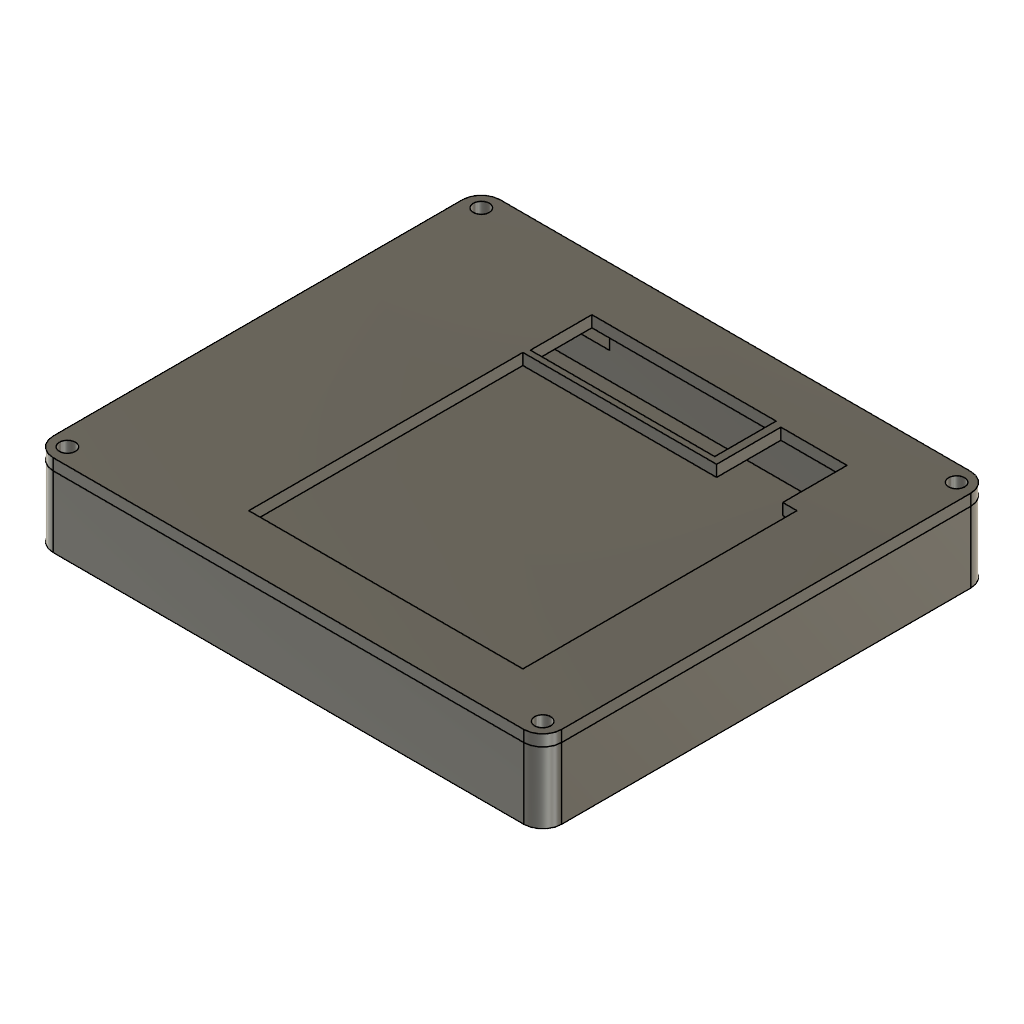
nexpad-case (Autodesk Fusion 360 design; units mm, degrees)
part number: 2026-11-12-22-31-13-139
Autodesk Fusion 360 part; units mm, degrees
sketch "Sketch1" plane through (0, 0, 0) normal (0, 0, 1) x (1, 0, 0)
sketch "base block" plane through (0, 0, 0) normal (0, 0, 1) x (1, 0, 0)
  line L0 (0, 0) -> (94, 0)
  line L1 (94, 0) -> (94, 81)
  line L2 (94, 81) -> (0, 81)
  line L3 (0, 81) -> (0, 0)
  line L4 (-7, -7) -> (100.6, -7)
  line L5 (100.6, -7) -> (100.6, 87.6)
  line L6 (100.6, 87.6) -> (-7, 87.6)
  line L7 (-7, 87.6) -> (-7, -7)
  dimension "d5" = 81
  dimension "d6" = 94
  dimension "d8" = 107.6
  dimension "d9" = 94.6
  constraint horizontal L0
  constraint vertical L1
  constraint horizontal L2
  constraint vertical L3
  constraint coincident L0.start L3.end
  constraint horizontal L4
  constraint vertical L5
  constraint horizontal L6
  constraint vertical L7
  measures "d5" distance of L0.end L1.end
  measures "d6" distance of L1.end L2.end
  measures "d8" distance of L4.start L4.end
  measures "d9" distance of L4.end L5.end
extrude "Extrude1" add sketch "base block" along normal blind 15 contours L0 L1 L2 L3 | L4 L5 L6 L7 makes body 1
fillet "Fillet1" radius 4 4 edges at (100.6, -7, 7.5) (100.6, 87.6, 7.5) (-7, 87.6, 7.5) (-7, -7, 7.5) on bodies 1
sketch "Sketch3" plane through (0, 0, 0) normal (0, 0, 1) x (1, 0, 0)
  line L0 (-0.35, -0.35) -> (93.95, -0.35)
  line L1 (93.95, -0.35) -> (93.95, 80.95)
  line L2 (93.95, 80.95) -> (-0.35, 80.95)
  line L3 (-0.35, 80.95) -> (-0.35, -0.35)
  dimension "d16" = 81.3
  dimension "d17" = 94.3
  dimension "d19" = 0.35
  dimension "d20" = 0.35
  constraint horizontal L0
  constraint vertical L1
  constraint horizontal L2
  constraint vertical L3
  measures "d16" distance of L0.start L2.end
  measures "d17" distance of L0.start L0.end
  measures "d19" distance of L3 origin
  measures "d20" distance of L0 origin
extrude "Extrude2" cut sketch "Sketch3" along normal blind 13 from surface at 2.4 bodies 1
fillet "Fillet2" radius 2.35 4 edges at (93.95, 80.95, 8.7) (-0.35, 80.95, 8.7) (93.95, -0.35, 8.7) (-0.35, -0.35, 8.7) on bodies 1
sketch "Sketch4" plane through (0, 0, 0) normal (0, 0, 1) x (1, 0, 0)
  line L0 (-1, -1) -> (3, -1)
  line L1 (3, -1) -> (3, 3)
  line L2 (3, 3) -> (-1, 3)
  line L3 (-1, 3) -> (-1, -1)
  line L4 (90.6, -1) -> (94.6, -1)
  line L5 (94.6, -1) -> (94.6, 3)
  line L6 (94.6, 3) -> (90.6, 3)
  line L7 (90.6, 3) -> (90.6, -1)
  line L8 (-1, 81.6) -> (3, 81.6)
  line L9 (3, 81.6) -> (3, 77.6)
  line L10 (3, 77.6) -> (-1, 77.6)
  line L11 (-1, 77.6) -> (-1, 81.6)
  line L12 (90.6, 81.6) -> (94.6, 81.6)
  line L13 (94.6, 81.6) -> (94.6, 77.6)
  line L14 (94.6, 77.6) -> (90.6, 77.6)
  line L15 (90.6, 77.6) -> (90.6, 81.6)
  dimension "d26" = 4
  dimension "d27" = 4
  dimension "d28" = 1
  dimension "d29" = 1
  dimension "d30" = 90.6
  dimension "d31" = 1
  dimension "d32" = 77.6
  dimension "d33" = 4
  dimension "d34" = 4
  dimension "d35" = 90.6
  dimension "d36" = 77.6
  constraint horizontal L0
  constraint vertical L1
  constraint horizontal L2
  constraint vertical L3
  constraint horizontal L4
  constraint vertical L5
  constraint horizontal L6
  constraint vertical L7
  constraint horizontal L8
  constraint vertical L9
  constraint horizontal L10
  constraint vertical L11
  constraint horizontal L12
  constraint vertical L13
  constraint horizontal L14
  constraint vertical L15
  measures "d26" distance of L0.start L0.end
  measures "d27" distance of L0.start L2.end
  measures "d28" distance of origin L3
  measures "d29" distance of origin L0
  measures "d30" distance of origin L7
  measures "d31" distance of origin L11
  measures "d32" distance of origin L10
  measures "d33" distance of L12.start L14.end
  measures "d34" distance of L12.start L12.end
  measures "d35" distance of origin L15
  measures "d36" distance of origin L14
extrude "Extrude3" add sketch "Sketch4" along normal blind 5.6 from surface at 2.4 bodies 1
sketch "Sketch5" plane through (0, 0, 0) normal (0, 0, 1) x (1, 0, 0)
  line L0 (4.8, 80) -> (26.8, 80)
  line L1 (26.8, 80) -> (26.8, 90)
  line L2 (26.8, 90) -> (4.8, 90)
  line L3 (4.8, 90) -> (4.8, 80)
  dimension "d40" = 22
  dimension "d41" = 10
  dimension "d42" = 4.8
  dimension "d43" = 80
  constraint horizontal L0
  constraint vertical L1
  constraint horizontal L2
  constraint vertical L3
  measures "d40" distance of L0.start L0.end
  measures "d41" distance of L0.start L2.end
  measures "d42" distance of origin L3
  measures "d43" distance of origin L0
extrude "Extrude4" cut sketch "Sketch5" along normal blind 10 from surface at 8 bodies 1
sketch "Sketch6" plane through (0, 0, 0) normal (0, 0, 1) x (1, 0, 0)
  circle A0 centre (-3.5, -3.5) radius 1.3
  circle A1 centre (97.1, -3.5) radius 1.3
  circle A2 centre (-3.5, 84.1) radius 1.3
  circle A3 centre (97.1, 84.1) radius 1.3
  dimension "d47" = 2.6
  dimension "d48" = 3.5
  dimension "d50" = 3.5
  dimension "d51" = 2.6
  dimension "d52" = 3.5
  dimension "d54" = 97.1
  dimension "d55" = 2.6
  dimension "d56" = 3.5
  dimension "d57" = 84.1
  dimension "d58" = 2.6
  dimension "d59" = 97.1
  dimension "d60" = 84.1
  measures "d47" diameter of A0
  measures "d48" vertical distance of origin A0.centre
  measures "d50" horizontal distance of origin A0.centre
  measures "d51" diameter of A1
  measures "d52" vertical distance of origin A1.centre
  measures "d54" horizontal distance of origin A1.centre
  measures "d55" diameter of A2
  measures "d56" horizontal distance of origin A2.centre
  measures "d57" vertical distance of origin A2.centre
  measures "d58" diameter of A3
  measures "d59" horizontal distance of origin A3.centre
  measures "d60" vertical distance of origin A3.centre
extrude "Extrude5" cut sketch "Sketch6" along normal blind 10 from surface at 6 bodies 1
sketch "Sketch7" plane through (0, 0, 0) normal (0, 0, 1) x (1, 0, 0)
  line L0 (-0.2, -0.2) -> (3.2, -0.2)
  line L1 (3.2, -0.2) -> (3.2, 3.2)
  line L2 (3.2, 3.2) -> (-0.2, 3.2)
  line L3 (-0.2, 3.2) -> (-0.2, -0.2)
  line L4 (90.4, -0.2) -> (93.8, -0.2)
  line L5 (93.8, -0.2) -> (93.8, 3.2)
  line L6 (93.8, 3.2) -> (90.4, 3.2)
  line L7 (90.4, 3.2) -> (90.4, -0.2)
  line L8 (-0.2, 77.4) -> (3.2, 77.4)
  line L9 (3.2, 77.4) -> (3.2, 80.8)
  line L10 (3.2, 80.8) -> (-0.2, 80.8)
  line L11 (-0.2, 80.8) -> (-0.2, 77.4)
  line L12 (90.4, 80.8) -> (93.8, 80.8)
  line L13 (93.8, 80.8) -> (93.8, 77.4)
  line L14 (93.8, 77.4) -> (90.4, 77.4)
  line L15 (90.4, 77.4) -> (90.4, 80.8)
  dimension "d64" = 3.4
  dimension "d65" = 3.4
  dimension "d66" = 0.2
  dimension "d67" = 0.2
  dimension "d68" = 3.4
  dimension "d69" = 3.4
  dimension "d71" = 90.4
  dimension "d72" = 3.4
  dimension "d73" = 3.4
  dimension "d74" = 0.2
  dimension "d75" = 77.4
  dimension "d76" = 3.4
  dimension "d77" = 3.4
  dimension "d78" = 90.4
  dimension "d79" = 77.4
  constraint horizontal L0
  constraint vertical L1
  constraint horizontal L2
  constraint vertical L3
  constraint horizontal L4
  constraint vertical L5
  constraint horizontal L6
  constraint vertical L7
  constraint horizontal L8
  constraint vertical L9
  constraint horizontal L10
  constraint vertical L11
  constraint horizontal L12
  constraint vertical L13
  constraint horizontal L14
  constraint vertical L15
  measures "d64" distance of L0.start L0.end
  measures "d65" distance of L0.start L2.end
  measures "d66" distance of origin L3
  measures "d67" distance of origin L0
  measures "d68" distance of L4.start L4.end
  measures "d69" distance of L4.start L6.end
  measures "d71" distance of origin L7
  measures "d72" distance of L8.start L10.end
  measures "d73" distance of L8.start L8.end
  measures "d74" distance of origin L11
  measures "d75" distance of origin L8
  measures "d76" distance of L12.start L12.end
  measures "d77" distance of L12.start L14.end
  measures "d78" distance of origin L15
  measures "d79" distance of origin L14
extrude "Extrude6" cut sketch "Sketch7" along normal blind 5.4 from surface at 9.7 bodies 1
sketch "Sketch8" plane through (0, 0, 0) normal (0, 0, 1) x (1, 0, 0)
  line L0 (-7, -7) -> (100.6, -7)
  line L1 (100.6, -7) -> (100.6, 87.6)
  line L2 (100.6, 87.6) -> (-7, 87.6)
  line L3 (-7, 87.6) -> (-7, -7)
  dimension "d83" = 107.6
  dimension "d84" = 94.6
  dimension "d85" = 7
  dimension "d86" = 7
  constraint horizontal L0
  constraint vertical L1
  constraint horizontal L2
  constraint vertical L3
  measures "d83" distance of L0.start L0.end
  measures "d84" distance of L0.start L2.end
  measures "d85" distance of origin L3
  measures "d86" distance of origin L0
extrude "Extrude7" add sketch "Sketch8" along normal blind 2.4 from surface at 15 separate body makes body 2
fillet "Fillet3" radius 4 4 edges at (100.6, -7, 16.2) (100.6, 87.6, 16.2) (-7, 87.6, 16.2) (-7, -7, 16.2) on bodies 2
sketch "Sketch9" plane through (0, 0, 0) normal (0, 0, 1) x (1, 0, 0)
  line L0 (27.4, 4) -> (85.4, 4)
  line L1 (85.4, 4) -> (85.4, 62)
  line L2 (85.4, 62) -> (27.4, 62)
  line L3 (27.4, 62) -> (27.4, 4)
  dimension "d92" = 58
  dimension "d93" = 58
  dimension "d94" = 4
  dimension "d95" = 27.4
  constraint horizontal L0
  constraint vertical L1
  constraint horizontal L2
  constraint vertical L3
  measures "d92" distance of L0.start L0.end
  measures "d93" distance of L0.start L2.end
  measures "d94" distance of origin L0
  measures "d95" distance of origin L3
extrude "Extrude8" cut sketch "Sketch9" along normal blind 5 from surface at 14 bodies 2
sketch "Sketch10" plane through (0, 0, 0) normal (0, 0, 1) x (1, 0, 0)
  line L0 (27.785, 63.215) -> (66.785, 63.215)
  line L1 (66.785, 63.215) -> (66.785, 76.215)
  line L2 (66.785, 76.215) -> (27.785, 76.215)
  line L3 (27.785, 76.215) -> (27.785, 63.215)
  dimension "d99" = 39
  dimension "d100" = 13
  dimension "d101" = 27.785
  dimension "d102" = 63.215
  constraint horizontal L0
  constraint vertical L1
  constraint horizontal L2
  constraint vertical L3
  measures "d99" distance of L0.start L0.end
  measures "d100" distance of L0.start L2.end
  measures "d101" distance of origin L3
  measures "d102" distance of origin L0
extrude "Extrude9" cut sketch "Sketch10" along normal blind 5 from surface at 14 bodies 2
sketch "Sketch11" plane through (0, 0, 0) normal (0, 0, 1) x (1, 0, 0)
  line L0 (68.4, 61.6) -> (82.4, 61.6)
  line L1 (82.4, 61.6) -> (82.4, 75.6)
  line L2 (82.4, 75.6) -> (68.4, 75.6)
  line L3 (68.4, 75.6) -> (68.4, 61.6)
  dimension "d106" = 14
  dimension "d107" = 14
  dimension "d108" = 68.4
  dimension "d109" = 61.6
  constraint horizontal L0
  constraint vertical L1
  constraint horizontal L2
  constraint vertical L3
  measures "d106" distance of L0.start L2.end
  measures "d107" distance of L0.start L0.end
  measures "d108" distance of origin L3
  measures "d109" distance of origin L0
extrude "Extrude10" cut sketch "Sketch11" along normal blind 5 from surface at 14 bodies 2
sketch "Sketch12" plane through (0, 0, 0) normal (0, 0, 1) x (1, 0, 0)
  line L0 (0, 0) -> (3, 0)
  line L1 (3, 0) -> (3, 3)
  line L2 (3, 3) -> (0, 3)
  line L3 (0, 3) -> (0, 0)
  line L4 (90.6, 0) -> (93.6, 0)
  line L5 (93.6, 0) -> (93.6, 3)
  line L6 (93.6, 3) -> (90.6, 3)
  line L7 (90.6, 3) -> (90.6, 0)
  line L8 (0, 77.6) -> (3, 77.6)
  line L9 (3, 77.6) -> (3, 80.6)
  line L10 (3, 80.6) -> (0, 80.6)
  line L11 (0, 80.6) -> (0, 77.6)
  line L12 (90.6, 80.6) -> (93.6, 80.6)
  line L13 (93.6, 80.6) -> (93.6, 77.6)
  line L14 (93.6, 77.6) -> (90.6, 77.6)
  line L15 (90.6, 77.6) -> (90.6, 80.6)
  dimension "d113" = 3
  dimension "d114" = 3
  dimension "d115" = 3
  dimension "d116" = 3
  dimension "d117" = 90.6
  dimension "d118" = 3
  dimension "d119" = 3
  dimension "d120" = 77.6
  dimension "d121" = 3
  dimension "d122" = 3
  dimension "d123" = 77.6
  dimension "d124" = 90.6
  constraint horizontal L0
  constraint vertical L1
  constraint horizontal L2
  constraint vertical L3
  constraint coincident L0.start L3.end
  constraint horizontal L4
  constraint vertical L5
  constraint horizontal L6
  constraint vertical L7
  constraint horizontal L8
  constraint vertical L9
  constraint horizontal L10
  constraint vertical L11
  constraint horizontal L12
  constraint vertical L13
  constraint horizontal L14
  constraint vertical L15
  measures "d113" distance of L0.start L0.end
  measures "d114" distance of L0.start L2.end
  measures "d115" distance of L4.start L4.end
  measures "d116" distance of L4.start L6.end
  measures "d117" distance of L0.start L7
  measures "d118" distance of L8.start L8.end
  measures "d119" distance of L8.start L10.end
  measures "d120" distance of L0.start L8
  measures "d121" distance of L12.start L12.end
  measures "d122" distance of L12.start L14.end
  measures "d123" distance of L0.start L14
  measures "d124" distance of L0.start L15
extrude "Extrude11" add sketch "Sketch12" against normal blind 5.1 from surface at 15 bodies 2
sketch "Sketch13" plane through (0, 0, 0) normal (0, 0, 1) x (1, 0, 0)
  circle A0 centre (-3.5, -3.5) radius 1.7
  circle A1 centre (97.1, -3.5) radius 1.7
  circle A2 centre (-3.5, 84.1) radius 1.7
  circle A3 centre (97.1, 84.1) radius 1.7
  dimension "d128" = 3.4
  dimension "d131" = 3.4
  dimension "d132" = 97.1
  dimension "d134" = 3.5
  dimension "d135" = 3.5
  dimension "d137" = 3.5
  dimension "d138" = 3.4
  dimension "d139" = 3.5
  dimension "d140" = 84.1
  dimension "d141" = 3.4
  dimension "d142" = 84.1
  dimension "d143" = 97.1
  measures "d128" diameter of A0
  measures "d131" diameter of A1
  measures "d132" horizontal distance of origin A1.centre
  measures "d134" vertical distance of origin A0.centre
  measures "d135" vertical distance of origin A1.centre
  measures "d137" horizontal distance of A0.centre origin
  measures "d138" diameter of A2
  measures "d139" horizontal distance of origin A2.centre
  measures "d140" vertical distance of origin A2.centre
  measures "d141" diameter of A3
  measures "d142" vertical distance of origin A3.centre
  measures "d143" horizontal distance of origin A3.centre
extrude "Extrude12" cut sketch "Sketch13" along normal blind 5 from surface at 14 bodies 2
